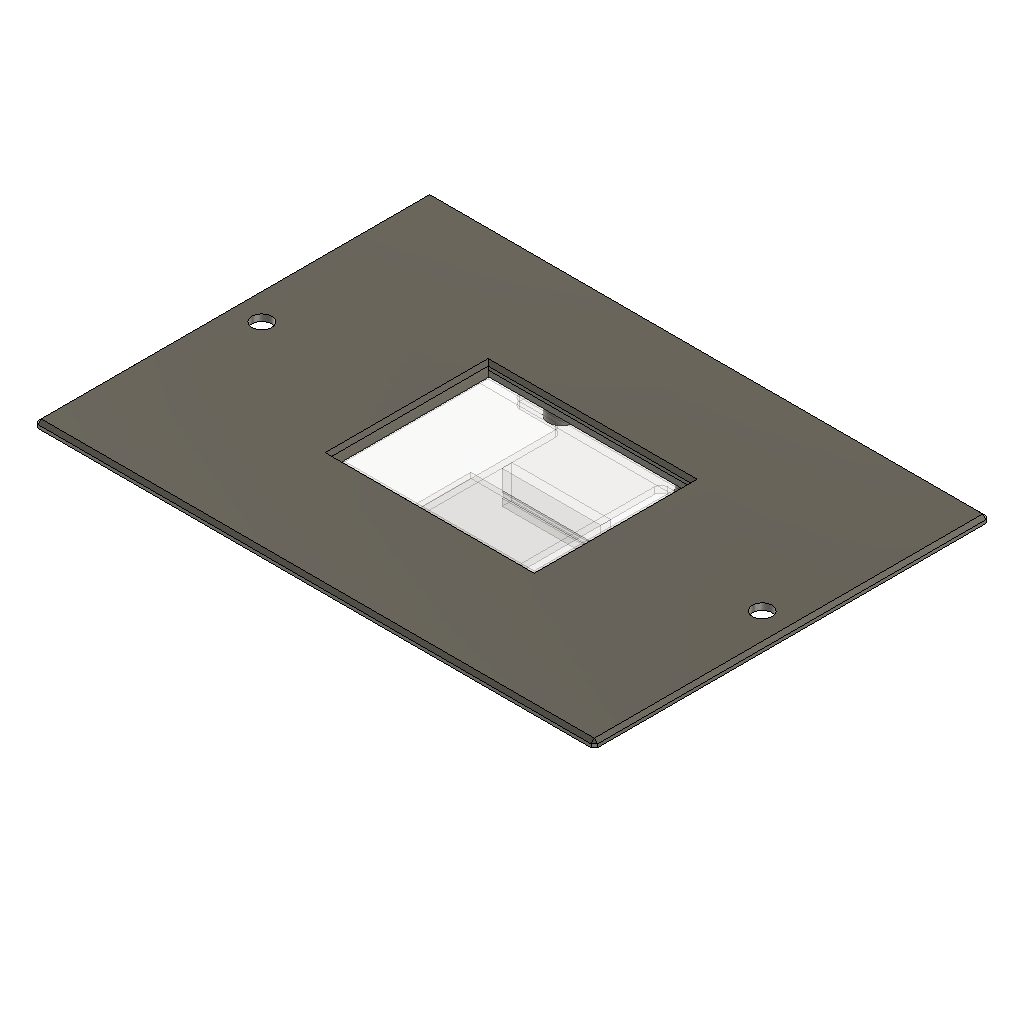
Vectaire MVHR Screen Panel (Autodesk Fusion 360 design; units mm, degrees)
part number: 2026-11-12-18-29-05-365
part number: 2026-11-12-18-29-33-035
part number: 2026-11-12-18-29-50-902
part number: 2026-11-12-19-22-07-273
part number: 2026-11-13-16-23-21-844
Autodesk Fusion 360 part; units mm, degrees
sketch "Sketch1" plane through (0, 0, 0) normal (0, 0, 1) x (1, 0, 0) in component "ESP32-C5 Screen"
  line L0 (42.75, 25) -> (-42.75, 25)
  line L1 (-42.75, 25) -> (-42.75, -25)
  line L2 (-42.75, -25) -> (42.75, -25)
  line L3 (42.75, -25) -> (42.75, 25)
  line L4 (42.75, 25) -> (-42.75, -25) construction
  line L5 (-42.75, 25) -> (42.75, -25) construction
  dimension "d1" = 85.5
  dimension "d2" = 50
  constraint horizontal L0
  constraint perpendicular L0 L1
  constraint parallel L0 L2
  constraint parallel L1 L3
  constraint coincident L4 origin
  constraint coincident L5 origin
  measures "d1" distance of L1.end L2.end
  measures "d2" distance of L0.end L1.end
extrude "Extrude1" add sketch "Sketch1" along normal blind 1.15 makes body 1 in component "ESP32-C5 Screen"
sketch "Sketch2" plane through (0, 0, 1.15) normal (0, 0, 1) x (-1, 0, 0) in component "ESP32-C5 Screen"
  line L0 (-42.75, 25) -> (-42.75, -25)
  line L1 (-42.75, -25) -> (42.75, -25)
  line L2 (42.75, -25) -> (42.75, 25)
  line L3 (42.75, 25) -> (-42.75, 25)
  circle A0 centre (39, -21) radius 1.65
  circle A1 centre (-39, -21) radius 1.65
  circle A2 centre (39, 21) radius 1.65
  circle A3 centre (-39, 21) radius 1.65
  line L4 (39, -21) -> (-39, -21)
  line L5 (-39, -21) -> (-39, 21)
  line L6 (-39, 21) -> (39, 21)
  line L7 (39, 21) -> (39, -21)
  line L8 (39, -21) -> (-39, 21)
  line L9 (-39, -21) -> (39, 21)
  dimension "d5" = 3.3
  dimension "d6" = 3.3
  dimension "d7" = 3.3
  dimension "d8" = 3.3
  dimension "d9" = 78
  dimension "d10" = 42
  dimension "d11" = 42
  dimension "d12" = 78
  constraint coincident A0.centre L4.start
  constraint coincident A1.centre L4.end
  constraint horizontal L4
  constraint coincident A3.centre L5.end
  constraint coincident A2.centre L6.end
  constraint perpendicular L4 L7
  constraint midpoint L9 origin
  measures "d5" diameter of A0
  measures "d6" diameter of A1
  measures "d7" diameter of A2
  measures "d8" diameter of A3
  measures "d9" horizontal distance of A0.centre A1.centre
  measures "d10" vertical distance of A1.centre A3.centre
  measures "d11" vertical distance of A0.centre A2.centre
  measures "d12" horizontal distance of A2.centre A3.centre
extrude "Extrude2" cut sketch "Sketch2" against normal blind 1.15 contours A0 L4 L7 | A0 L7 L8 | A0 L4 L8 | A2 L6 L7 | A2 L7 L9 | A1 L4 L9 | A1 L4 L5 | A2 L6 L9 | A1 L5 L9 | A3 L6 L8 | A3 L5 L8 | A3 L5 L6 bodies 1 in component "ESP32-C5 Screen"
fillet "Fillet1" radius 3 4 edges at (-42.75, 25, 0.575) (-42.75, -25, 0.575) (42.75, -25, 0.575) (42.75, 25, 0.575) on bodies 1 in component "ESP32-C5 Screen"
sketch "Sketch3" plane through (0, 0, 1.15) normal (0, 0, 1) x (-1, 0, 0) in component "ESP32-C5 Screen"
  arc A0 (-42.75, -22) -> (-39.75, -25) centre (-39.75, -22) ccw
  line L0 (-39.75, -25) -> (39.75, -25)
  arc A1 (39.75, -25) -> (42.75, -22) centre (39.75, -22) ccw
  line L1 (42.75, -22) -> (42.75, 22)
  arc A2 (42.75, 22) -> (39.75, 25) centre (39.75, 22) ccw
  line L2 (39.75, 25) -> (-39.75, 25)
  arc A3 (-39.75, 25) -> (-42.75, 22) centre (-39.75, 22) ccw
  line L3 (-42.75, 22) -> (-42.75, -22)
  circle A4 centre (39, -21) radius 1.65
  circle A5 centre (-39, 21) radius 1.65
  circle A6 centre (-39, -21) radius 1.65
  circle A7 centre (39, 21) radius 1.65
  line L4 (-35.25, -25) -> (34.75, -25)
  line L5 (34.75, -25) -> (34.75, 25)
  line L6 (34.75, 25) -> (-35.25, 25)
  line L7 (-35.25, 25) -> (-35.25, -25)
  line L8 (-35.25, -25) -> (34.75, 25) construction
  line L9 (34.75, -25) -> (-35.25, 25) construction
  dimension "d17" = 70
  dimension "d18" = 50
  dimension "d21" = 7.5
  constraint horizontal L4
  constraint perpendicular L4 L5
  constraint parallel L4 L6
  constraint parallel L5 L7
  measures "d17" distance of L5.end L6.end
  measures "d18" distance of L4.end L5.end
  measures "d21" distance of L3 L7
extrude "Extrude3" add sketch "Sketch3" along normal blind 4.75 contours L0 L2 L4 L5 L6 L7 bodies 1 in component "ESP32-C5 Screen"
sketch "Sketch1 (2)" plane through (0, 0, 5.9) normal (0, 0, 1) x (-1, 0, 0) in component "PSU pcb"
  line L0 (-35.25, 25) -> (-35.25, -25)
  line L1 (-35.25, -25) -> (34.75, -25)
  line L2 (34.75, -25) -> (34.75, 25)
  line L3 (34.75, 25) -> (-35.25, 25)
  line L4 (-25, -12.5) -> (25, -12.5)
  line L5 (25, -12.5) -> (25, 12.5)
  line L6 (25, 12.5) -> (-25, 12.5)
  line L7 (-25, 12.5) -> (-25, -12.5)
  line L8 (-25, -12.5) -> (25, 12.5) construction
  line L9 (25, -12.5) -> (-25, 12.5) construction
  dimension "d22" = 50
  dimension "d23" = 25
  constraint horizontal L4
  constraint perpendicular L4 L5
  constraint parallel L4 L6
  constraint parallel L5 L7
  constraint coincident L8 origin
  constraint coincident L9 origin
  measures "d22" distance of L5.end L6.end
  measures "d23" distance of L4.end L5.end
extrude "Extrude1'" add sketch "Sketch1 (2)" along normal blind 1.6 separate body contours L4 L5 L6 L7 makes body 2 in component "PSU pcb"
sketch "Sketch1 (3)" plane through (0, 0, 5.9) normal (0, 0, 1) x (-1, 0, 0) in component "Front Panel"
  line L0 (-35.25, 25) -> (-35.25, -25)
  line L1 (-35.25, -25) -> (34.75, -25)
  line L2 (34.75, -25) -> (34.75, 25)
  line L3 (34.75, 25) -> (-35.25, 25)
  line L4 (-85, -60) -> (85, -60)
  line L5 (85, -60) -> (85, 60)
  line L6 (85, 60) -> (-85, 60)
  line L7 (-85, 60) -> (-85, -60)
  line L8 (-85, -60) -> (85, 60) construction
  line L9 (85, -60) -> (-85, 60) construction
  circle A0 centre (76, 0) radius 3
  circle A1 centre (-76, 0) radius 3
  line L10 (76, 0) -> (-76, 0)
  line L11 (-85, 0) -> (85, 0)
  dimension "d26" = 170
  dimension "d27" = 120
  dimension "d28" = 6
  dimension "d29" = 6
  dimension "d30" = 152
  constraint horizontal L4
  constraint perpendicular L4 L5
  constraint parallel L4 L6
  constraint parallel L5 L7
  constraint coincident L8 origin
  constraint coincident L9 origin
  constraint coincident A0.centre L10.start
  constraint coincident A1.centre L10.end
  constraint horizontal L10
  constraint midpoint L7 L11.start
  constraint midpoint L5 L11.end
  constraint midpoint L10 L11
  measures "d26" distance of L5.end L6.end
  measures "d27" distance of L4.end L5.end
  measures "d28" diameter of A0
  measures "d29" diameter of A1
  measures "d30" distance of A0.centre A1.centre
extrude "Extrude1''" add sketch "Sketch1 (3)" along normal blind 2 separate body contours L0 L2 L3 L10 L11 | L0 L2 L3 L5 L6 L7 A0 A1 L10 L11 | L0 L1 L2 L10 L11 | L0 L1 L2 L4 L5 L7 A0 A1 L10 L11 makes body 3 in component "Front Panel"
sketch "Sketch1 (1)" plane through (0, 0, 7.9) normal (0, 0, 1) x (-1, 0, 0) in component "Front Panel"
  circle A0 centre (-76, 0) radius 3
  circle A1 centre (76, 0) radius 3
  line L0 (-85, 60) -> (-85, -60)
  line L1 (-85, -60) -> (85, -60)
  line L2 (85, -60) -> (85, 60)
  line L3 (85, 60) -> (-85, 60)
  line L4 (-30.5, -23.7452) -> (36, -23.7452)
  line L5 (36, -23.7452) -> (36, 23.7548)
  line L6 (36, 23.7548) -> (-30.5, 23.7548)
  line L7 (-30.5, 23.7548) -> (-30.5, -23.7452)
  line L8 (-30.5, -23.7452) -> (36, 23.7548) construction
  line L9 (36, -23.7452) -> (-30.5, 23.7548) construction
  line L10 (36, 23.7548) -> (31, 23.7548)
  line L11 (31, 23.7548) -> (31, -25.25)
  line L12 (31, -25.25) -> (36, -25.25)
  line L13 (36, -25.25) -> (36, 23.7548)
  point P0 (2.75, 0.0048)
  dimension "d33" = 66.5
  dimension "d34" = 47.5
  dimension "d152" = 5
  dimension "d153" = 54.5
  constraint horizontal L4
  constraint perpendicular L4 L5
  constraint parallel L4 L6
  constraint parallel L5 L7
  constraint horizontal L10
  constraint vertical L11
  constraint horizontal L12
  constraint vertical L13
  constraint midpoint L8 P0
  measures "d33" distance of L5.end L6.end
  measures "d34" distance of L4.end L5.end
  measures "d152" distance of L5.end L10.end
  measures "d153" distance of L0 L7
extrude "Extrude2'" cut sketch "Sketch1 (1)" against normal blind 2 contours L4 L6 L7 L11 bodies 3 in component "Front Panel"
sketch "Sketch2 (2)" plane through (0, 0, 5.9) normal (0, 0, -1) x (1, 0, 0) in component "Front Panel"
  line L0 (-85, 60) -> (-85, -60)
  line L1 (-85, -60) -> (85, -60)
  line L2 (85, -60) -> (85, 60)
  line L3 (85, 60) -> (-85, 60)
  line L4 (30.5, -23.7452) -> (-31, -23.7452)
  line L5 (-31, 23.7548) -> (30.5, 23.7548)
  line L6 (30.5, 23.7548) -> (30.5, -23.7452)
  circle A0 centre (76, 0) radius 3
  circle A1 centre (-76, 0) radius 3
  circle A2 centre (36, 21) radius 3.5
  circle A3 centre (36, -21) radius 3.5
  circle A4 centre (-42, 21) radius 3.75
  circle A5 centre (-42, -21) radius 3.75
  line L7 (-42, 21) -> (36, -21)
  line L8 (36, -21) -> (36, 21)
  line L9 (36, 21) -> (-42, -21)
  line L10 (-42, -21) -> (-42, 21)
  line L11 (36, 21) -> (-42, 21)
  line L12 (-42, -21) -> (36, -21)
  line L13 (-42, 0) -> (36, 0)
  circle A6 centre (36, -21) radius 2.15
  circle A7 centre (-42, -21) radius 2.15
  circle A8 centre (-42, 21) radius 2.15
  circle A9 centre (36, 21) radius 2.15
  line L14 (-31, -23.7452) -> (-31, 23.7548)
  dimension "d45" = 7
  dimension "d46" = 7
  dimension "d47" = 7.5
  dimension "d48" = 7.5
  dimension "d49" = 78
  dimension "d50" = 78
  dimension "d51" = 42
  dimension "d52" = 42
  dimension "d55" = 49
  dimension "d121" = 4.3
  dimension "d122" = 4.3
  dimension "d123" = 4.3
  dimension "d124" = 4.3
  constraint coincident A4.centre L7.start
  constraint coincident A3.centre L7.end
  constraint coincident A2.centre L8.end
  constraint coincident A5.centre L9.end
  constraint horizontal L12
  constraint midpoint L10 L13.start
  constraint midpoint L8 L13.end
  constraint perpendicular L10 L12
  constraint concentric A4 A8
  measures "d45" diameter of A2
  measures "d46" diameter of A3
  measures "d47" diameter of A4
  measures "d48" diameter of A5
  measures "d49" distance of A3.centre A5.centre
  measures "d50" horizontal distance of A2.centre A4.centre
  measures "d51" vertical distance of A4.centre A5.centre
  measures "d52" vertical distance of A2.centre A3.centre
  measures "d55" distance of L2 L8
  measures "d121" diameter of A6
  measures "d122" diameter of A7
  measures "d123" diameter of A8
  measures "d124" diameter of A9
extrude "Extrude3'" add sketch "Sketch2 (2)" along normal blind 4.5 contours A3 L8 L12 A6 | A3 L7 L12 A6 | A5 L9 L12 A7 | A5 L10 L12 A7 | A3 L7 L8 A6 | A5 L9 L10 A7 | A2 L8 L9 A9 | A2 L9 L11 A9 | A2 L8 L11 A9 | A4 L7 L11 A8 | A4 L7 L10 A8 | A4 L10 L11 A8 bodies 3 in component "Front Panel"
chamfer "Chamfer2" distance 1 angle 45 12 edges at (-0.25, -23.7548, 7.9) (30.5, -0.0048, 7.9) (-0.25, 23.7452, 7.9) (0, -60, 7.9) (0, 60, 7.9) (-85, 60, 6.9) (-85, 0, 7.9) (85, 60, 6.9) (85, -60, 6.9) (-85, -60, 6.9) (85, 0, 7.9) (-31, -0.0048, 7.9) tangent chain off on bodies 3 in component "Front Panel"
sketch "Sketch4" plane through (0, 0, 5.9) normal (0, 0, -1) x (1, 0, 0) in component "Front Panel"
  line L0 (-69, -51.5) -> (69, -51.5)
  line L1 (69, -51.5) -> (69, 51.5)
  line L2 (69, 51.5) -> (-69, 51.5)
  line L3 (-69, 51.5) -> (-69, -51.5)
  line L4 (-69, -51.5) -> (69, 51.5) construction
  line L5 (69, -51.5) -> (-69, 51.5) construction
  circle A0 centre (20, -35) radius 4
  circle A1 centre (-20, -35) radius 4
  circle A2 centre (20, 35) radius 4
  circle A3 centre (-20, 35) radius 4
  line L6 (20, -35) -> (-20, -35)
  line L7 (-20, -35) -> (-20, 35)
  line L8 (-20, 35) -> (20, 35)
  line L9 (20, 35) -> (20, -35)
  line L10 (-20, 35) -> (20, -35)
  line L11 (-20, -35) -> (20, 35)
  circle A4 centre (20, 35) radius 2.05
  circle A5 centre (-20, 35) radius 2.05
  circle A6 centre (20, -35) radius 2.05
  circle A7 centre (-20, -35) radius 2.05
  dimension "d60" = 103
  dimension "d61" = 138
  dimension "d69" = 8
  dimension "d70" = 8
  dimension "d71" = 8
  dimension "d72" = 8
  dimension "d74" = 40
  dimension "d75" = 70
  dimension "d129" = 4.1
  dimension "d130" = 4.1
  dimension "d131" = 4.1
  dimension "d132" = 4.1
  constraint horizontal L0
  constraint perpendicular L0 L1
  constraint parallel L0 L2
  constraint parallel L1 L3
  constraint coincident L4 origin
  constraint coincident L5 origin
  constraint horizontal L6
  constraint vertical L7
  constraint horizontal L8
  constraint vertical L9
  constraint coincident A3.centre L7.end
  constraint coincident A2.centre L8.end
  constraint coincident A0.centre L6.start
  constraint coincident A1.centre L6.end
  constraint midpoint L10 origin
  constraint concentric A2 A4
  constraint concentric A3 A5
  constraint concentric A0 A6
  constraint concentric A1 A7
  measures "d60" distance of L0.end L1.end
  measures "d61" distance of L1.end L2.end
  measures "d69" diameter of A0
  measures "d70" diameter of A1
  measures "d71" diameter of A2
  measures "d72" diameter of A3
  measures "d74" distance of A0.centre A1.centre
  measures "d75" distance of A1.centre A3.centre
  measures "d129" diameter of A4
  measures "d130" diameter of A5
  measures "d131" diameter of A6
  measures "d132" diameter of A7
extrude "Extrude5" add sketch "Sketch4" along normal blind 12 contours A0 L6 L9 A6 | A0 L9 L10 A6 | A0 L6 L10 A6 | A2 L8 L9 A4 | A2 L9 L11 A4 | A1 L6 L11 A7 | A1 L6 L7 A7 | A2 L8 L11 A4 | A1 L7 L11 A7 | A3 L8 L10 A5 | A3 L7 L10 A5 | A3 L7 L8 A5 bodies 3 in component "Front Panel"
sketch "Sketch1 (4)" plane through (0, 0, 5.9) normal (0, 0, -1) x (1, 0, 0) in component "PSU Plate"
  circle A0 centre (20, 35) radius 4
  circle A1 centre (-20, 35) radius 4
  line L0 (84, -60) -> (85, -59)
  line L1 (85, -59) -> (85, 59)
  line L2 (85, 59) -> (84, 60)
  line L3 (84, 60) -> (-84, 60)
  line L4 (-84, 60) -> (-85, 59)
  line L5 (-85, 59) -> (-85, -59)
  line L6 (-85, -59) -> (-84, -60)
  line L7 (-84, -60) -> (84, -60)
  circle A2 centre (-42, -21) radius 3.75
  circle A3 centre (-42, 21) radius 3.75
  line L8 (30.5, -23.7452) -> (-31, -23.7452)
  line L9 (-31, 23.7548) -> (30.5, 23.7548)
  line L10 (30.5, 23.7548) -> (30.5, -23.7452)
  circle A4 centre (76, 0) radius 3
  circle A5 centre (-76, 0) radius 3
  circle A6 centre (20, -35) radius 4
  circle A7 centre (-20, -35) radius 4
  line L11 (29.9847, -42.7129) -> (-30.0153, -42.7129)
  line L12 (-30.0153, -42.7129) -> (-30.0153, 42.2871)
  line L13 (-30.0153, 42.2871) -> (29.9847, 42.2871)
  line L14 (29.9847, 42.2871) -> (29.9847, -42.7129)
  line L15 (29.9847, -42.7129) -> (-30.0153, 42.2871)
  line L16 (29.9847, 42.2871) -> (-30.0153, -42.7129)
  line L17 (-31, -23.7452) -> (-31, 23.7548)
  circle A8 centre (36, 21) radius 3.5
  circle A9 centre (36, -21) radius 3.5
  dimension "d78" = 60
  dimension "d79" = 85
  constraint horizontal L11
  constraint vertical L12
  constraint horizontal L13
  constraint vertical L14
  measures "d78" distance of L11.start L11.end
  measures "d79" distance of L11.start L13.end
sketch "Sketch2 (3)" plane through (0, 0, 5.9) normal (0, 0, -1) x (1, 0, 0) in component "PSU Plate"
  line L0 (-20, -35) -> (20, -35)
  line L1 (20, -35) -> (20, 35)
  line L2 (20, 35) -> (-20, 35)
  line L3 (-20, 35) -> (-20, -35)
  line L4 (-20, -35) -> (20, 35) construction
  line L5 (20, -35) -> (-20, 35) construction
  circle A0 centre (20, -35) radius 2
  circle A1 centre (-20, -35) radius 2
  circle A2 centre (-20, 35) radius 2
  circle A3 centre (20, 35) radius 2
  dimension "d80" = 40
  dimension "d81" = 70
  dimension "d82" = 4
  dimension "d83" = 4
  dimension "d84" = 4
  dimension "d85" = 4
  constraint horizontal L0
  constraint perpendicular L0 L1
  constraint parallel L0 L2
  constraint parallel L1 L3
  constraint coincident L4 origin
  constraint coincident L5 origin
  constraint coincident L0.end L1.start
  constraint coincident L0.start L3.end
  constraint coincident L2.end L3.start
  constraint coincident L1.end L2.start
  measures "d80" distance of L1.end L2.end
  measures "d81" distance of L0.end L1.end
  measures "d82" diameter of A0
  measures "d83" diameter of A1
  measures "d84" diameter of A2
  measures "d85" diameter of A3
extrude "Extrude2''" add sketch "Sketch1 (4)" against normal blind 2 separate body contours A0 L16 | A0 A1 L9 L13 L15 L16 | A0 L16 | A0 L9 L14 L16 | L9 L15 L16 | L8 L9 L14 L15 L16 | L8 L9 L12 L15 L16 | A1 L9 L12 L15 | L8 L15 L16 | A1 L15 | A1 L15 | L8 A6 L14 L15 | L8 A6 A7 L11 L15 L16 | L8 A7 L12 L16 | A6 L15 | A6 L15 | A7 L16 | A7 L16 makes body 4 in component "PSU Plate"
fillet "Fillet1'" radius 2 4 edges at (29.9847, -42.2871, 6.9) (-30.0153, -42.2871, 6.9) (-30.0153, 42.7129, 6.9) (29.9847, 42.7129, 6.9) on bodies 4 in component "PSU Plate"
sketch "Sketch4 (2)" plane through (0, 0, 7.9) normal (0, 0, 1) x (1, 0, 0) in component "PSU Plate"
  arc A0 (29.9847, 40.7129) -> (27.9847, 42.7129) centre (27.9847, 40.7129) ccw
  line L0 (29.9847, -40.2871) -> (29.9847, 40.7129)
  arc A1 (27.9847, -42.2871) -> (29.9847, -40.2871) centre (27.9847, -40.2871) ccw
  line L1 (-28.0153, -42.2871) -> (27.9847, -42.2871)
  arc A2 (-30.0153, -40.2871) -> (-28.0153, -42.2871) centre (-28.0153, -40.2871) ccw
  line L2 (-30.0153, 40.7129) -> (-30.0153, -40.2871)
  arc A3 (-28.0153, 42.7129) -> (-30.0153, 40.7129) centre (-28.0153, 40.7129) ccw
  line L3 (27.9847, 42.7129) -> (-28.0153, 42.7129)
  line L4 (-15, 15) -> (15, 15)
  line L5 (15, 15) -> (15, 12)
  line L6 (15, 12) -> (-15, 12)
  line L7 (-15, 12) -> (-15, 15)
  line L8 (-15, -12) -> (15, -12)
  line L9 (15, -12) -> (15, -15)
  line L10 (15, -15) -> (-15, -15)
  line L11 (-15, -15) -> (-15, -12)
  line L12 (-15, 12) -> (-15, -12)
  line L13 (15, 12) -> (15, -12)
  line L14 (-15, 12) -> (15, -12)
  line L15 (-15, -12) -> (15, 12)
  dimension "d103" = 30
  dimension "d104" = 3
  dimension "d105" = 30
  dimension "d106" = 3
  dimension "d108" = 24
  constraint horizontal L4
  constraint vertical L5
  constraint horizontal L6
  constraint vertical L7
  constraint horizontal L8
  constraint vertical L9
  constraint horizontal L10
  constraint vertical L11
  constraint perpendicular L6 L12
  constraint midpoint L15 origin
  measures "d103" distance of L4.start L4.end
  measures "d104" distance of L4.start L6.end
  measures "d105" distance of L8.end L8.start
  measures "d106" distance of L10.end L8.start
  measures "d108" distance of L6.end L8.start
extrude "Extrude4" add sketch "Sketch4 (2)" against normal blind 12 contours L4 L5 L6 L7 | L8 L9 L10 L11 bodies 4 in component "PSU Plate"
sketch "Sketch5" plane through (-15, 0, 0) normal (-1, 0, 0) x (0, -1, 0) in component "PSU Plate"
  line L0 (-12, -4.1) -> (-12, 5.9)
  line L1 (-15, -4.1) -> (-12, -4.1)
  line L2 (-15, 5.9) -> (-15, -4.1)
  line L3 (12.5, -2) -> (-12.5, -2)
  line L4 (-12.5, -2) -> (-12.5, -0.4)
  line L5 (-12.5, -0.4) -> (12.5, -0.4)
  line L6 (12.5, -0.4) -> (12.5, -2)
  line L7 (-12, 5.9) -> (-15, 5.9)
  dimension "d111" = 25
  dimension "d112" = 1.6
  constraint horizontal L3
  constraint vertical L4
  constraint horizontal L5
  constraint vertical L6
  measures "d111" distance of L3.start L3.end
  measures "d112" distance of L3.start L5.end
extrude "Extrude5'" cut sketch "Sketch5" against normal blind 30 contours L0 L3 L4 L5 | L0 L3 L5 L6 bodies 4 in component "PSU Plate"
extrude "Extrude6" add 4 faces at (19.5573, 35.607, 5.9) (-20.1475, 34.3639, 5.9) (19.8525, -35.6361, 5.9) (-19.7504, -35.6361, 5.9) along direction (0, 0, -1) blind 3 on bodies 3 bodies 3 in component "Front Panel"
extrude "Extrude6'" cut sketch "Sketch2 (3)" against normal blind 2 contours L0 L3 A1 | L0 L3 A1 | L0 L1 A0 | L0 L1 A0 | L2 L3 A2 | L2 L3 A2 | L1 L2 A3 | L1 L2 A3 bodies 4 in component "PSU Plate"
sketch "Sketch6" plane through (0, 0, 5.9) normal (0, 0, -1) x (1, 0, 0) in component "PSU Plate"
  arc A0 (27.9847, -42.7129) -> (29.9847, -40.7129) centre (27.9847, -40.7129) ccw
  line L0 (29.9847, -40.7129) -> (29.9847, 40.2871)
  arc A1 (29.9847, 40.2871) -> (27.9847, 42.2871) centre (27.9847, 40.2871) ccw
  line L1 (27.9847, 42.2871) -> (-28.0153, 42.2871)
  arc A2 (-28.0153, 42.2871) -> (-30.0153, 40.2871) centre (-28.0153, 40.2871) ccw
  line L2 (-30.0153, 40.2871) -> (-30.0153, -40.7129)
  arc A3 (-30.0153, -40.7129) -> (-28.0153, -42.7129) centre (-28.0153, -40.7129) ccw
  line L3 (-28.0153, -42.7129) -> (27.9847, -42.7129)
  line L4 (15, -12) -> (15, -15)
  line L5 (15, -15) -> (-15, -15)
  line L6 (-15, -15) -> (-15, -12)
  line L7 (-15, -12) -> (15, -12)
  line L8 (15, 15) -> (15, 12)
  line L9 (15, 12) -> (-15, 12)
  line L10 (-15, 12) -> (-15, 15)
  line L11 (-15, 15) -> (15, 15)
  circle A4 centre (-20, -35) radius 2
  circle A5 centre (20, 35) radius 2
  circle A6 centre (20, -35) radius 2
  circle A7 centre (-20, 35) radius 2
  line L12 (29.9847, 29.7871) -> (14.9847, 29.7871)
  line L13 (14.9847, 29.7871) -> (14.9847, -30.2129)
  line L14 (14.9847, -30.2129) -> (29.9847, -30.2129)
  line L15 (29.9847, -30.2129) -> (29.9847, 29.7871)
  line L16 (-30.0153, 29.7871) -> (-15.0153, 29.7871)
  line L17 (-15.0153, 29.7871) -> (-15.0153, -30.2129)
  line L18 (-15.0153, -30.2129) -> (-30.0153, -30.2129)
  line L19 (-30.0153, -30.2129) -> (-30.0153, 29.7871)
  dimension "d137" = 15
  dimension "d138" = 60
  dimension "d139" = 12.5
  dimension "d140" = 15
  dimension "d141" = 60
  constraint horizontal L12
  constraint vertical L13
  constraint horizontal L14
  constraint vertical L15
  constraint coincident L0 L12.start
  constraint horizontal L16
  constraint vertical L17
  constraint horizontal L18
  constraint vertical L19
  constraint coincident L2 L16.start
  measures "d137" distance of L12.start L12.end
  measures "d138" distance of L12.start L14.end
  measures "d139" distance of A1.end L12
  measures "d140" distance of L16.start L16.end
  measures "d141" distance of L16.start L18.end
extrude "Extrude7" cut sketch "Sketch6" against normal blind 2 contours L0 L4 L5 L7 L8 L9 L11 L12 L13 L14 L15 | L2 L16 L17 L18 L19 | L4 L5 L7 L13 | L8 L9 L11 L13 bodies 4 in component "PSU Plate"
fillet "Fillet2" radius 2 tangency weight 0.80886 8 edges at (29.9847, 30.2129, 6.9) (-30.0153, 30.2129, 6.9) (-30.0153, -29.7871, 6.9) (29.9847, -29.7871, 6.9) (14.9847, -29.7871, 6.9) (-15.0153, -29.7871, 6.9) (-15.0153, 30.2129, 6.9) (14.9847, 30.2129, 6.9) on bodies 4 in component "PSU Plate"
sketch "Sketch3 (2)" plane through (0, 0, -60.572) normal (0, 0, 1) x (-1, 0, 0)
  line L0 (-43.4145, 3.3547) -> (-43.4145, -46.6453)
  line L1 (-43.4145, -46.6453) -> (26.5855, -46.6453)
  line L2 (26.5855, -46.6453) -> (26.5855, 3.3547)
  line L3 (26.5855, 3.3547) -> (-43.4145, 3.3547)
  line L4 (-39.9145, 0.3547) -> (18.0855, 0.3547)
  line L5 (18.0855, 0.3547) -> (18.0855, -43.6453)
  line L6 (18.0855, -43.6453) -> (-39.9145, -43.6453)
  line L7 (-39.9145, -43.6453) -> (-39.9145, 0.3547)
  dimension "d146" = 58
  dimension "d147" = 44
  dimension "d148" = 8.5
  dimension "d149" = 3
  constraint horizontal L4
  constraint vertical L5
  constraint horizontal L6
  constraint vertical L7
  measures "d146" distance of L5.end L6.end
  measures "d147" distance of L4.end L5.end
  measures "d148" distance of L2 L5
  measures "d149" distance of L3 L4
extrude "Extrude5''" cut sketch "Sketch3 (2)" against normal blind 0.5 contours L4 L5 L6 L7 sketch seen with x (1, 0, 0) y (0, 1, 0) z (0, 0, 1) at (-8.1645, -21.6453, 66.472) bodies 1 in component "ESP32-C5 Screen"
sketch "Sketch6 (2)" plane through (0, 0, 5.9) normal (0, 0, 1) x (1, 0, 0) in component "Front Panel"
  line L0 (-32, -25) -> (32, -25)
  line L1 (32, -25) -> (32, 25)
  line L2 (32, 25) -> (-32, 25)
  line L3 (-32, 25) -> (-32, -25)
  line L4 (32, 25) -> (-32, -25)
  line L5 (32, -25) -> (-32, 25)
  line L6 (-31, -24) -> (31, -24)
  line L7 (31, -24) -> (31, 24)
  line L8 (31, 24) -> (-31, 24)
  line L9 (-31, 24) -> (-31, -24)
  circle A0 centre (20, -35) radius 4
  circle A1 centre (-20, -35) radius 4
  line L10 (84, 60) -> (85, 59)
  line L11 (85, 59) -> (85, -59)
  line L12 (85, -59) -> (84, -60)
  line L13 (84, -60) -> (-84, -60)
  line L14 (-84, -60) -> (-85, -59)
  line L15 (-85, -59) -> (-85, 59)
  line L16 (-85, 59) -> (-84, 60)
  line L17 (-84, 60) -> (84, 60)
  circle A2 centre (36, -21) radius 3.5
  circle A3 centre (36, 21) radius 3.5
  line L18 (30.5, 23.7452) -> (-31, 23.7452)
  line L19 (-31, 23.7452) -> (-31, -23.7548)
  line L20 (-31, -23.7548) -> (30.5, -23.7548)
  line L21 (30.5, -23.7548) -> (30.5, 23.7452)
  circle A4 centre (76, 0) radius 3
  circle A5 centre (-76, 0) radius 3
  circle A6 centre (-42, -21) radius 3.75
  circle A7 centre (-42, 21) radius 3.75
  circle A8 centre (20, 35) radius 4
  circle A9 centre (-20, 35) radius 4
  dimension "d154" = 64
  dimension "d155" = 50
  dimension "d156" = -1
  constraint horizontal L0
  constraint vertical L1
  constraint horizontal L2
  constraint vertical L3
  constraint midpoint L4 origin
  measures "d154" distance of L0.start L0.end
  measures "d155" distance of L0.start L2.end
extrude "Extrude8" add sketch "Sketch6 (2)" against normal blind 2 contours L0 L4 L5 L6 | L3 L4 L5 L6 L8 L9 L19 | L1 L4 L5 L6 L7 L8 | L2 L4 L5 L8 bodies 3 in component "Front Panel"
component "ESP32-C5 Screen" placed x (1, 0, 0) y (0, 1, 0) z (0, 0, 1) at (8.1645, 21.6453, -66.472)
component "Front Panel" placed x (1, 0, 0) y (0, 1, 0) z (0, 0, 1) at (11.1645, 21.6453, -66.372)
component "PSU pcb" placed x (1, 0, 0) y (0, 1, 0) z (0, 0, 1) at (11.1645, 21.6453, -86.272)
component "PSU Plate" placed x (1, 0, 0) y (0, 1, 0) z (0, 0, 1) at (11.1645, 21.6453, -78.372)
